Autodesk Inventor part; units mm, degrees
(part 2 of 2)
sketch "Sketch22" plane through (0, 5, 0) normal (0, 1, 0) x (1, 0, 0)
  circle A0 centre (-16, 40) radius 1.75 projected
  circle A1 centre (-21.2113, 35) radius 1.25 projected
  circle A2 centre (-21.2113, 15) radius 1.25 projected
  circle A3 centre (-16, 10) radius 1.75 projected
  circle A4 centre (-41.2113, 15) radius 1.25 projected
  circle A5 centre (-41.2113, 35) radius 1.25 projected
  circle A6 centre (-46.8088, 40.126) radius 1.75 projected
  circle A7 centre (-46.8088, 9.874) radius 1.75 projected
  circle A8 centre (-67.6238, 7.0035) radius 1.75 projected
  circle A9 centre (-78.624, 10.0035) radius 2.25 projected
  circle A10 centre (-78.624, 39.9965) radius 2.25 projected
  circle A11 centre (-67.6238, 42.9965) radius 1.75 projected
  circle A12 centre (-83.6239, 34.9965) radius 1.75 projected
  circle A13 centre (-83.6239, 15.0035) radius 1.75 projected
  circle A14 centre (-103.6239, 15.0035) radius 1.75 projected
  circle A15 centre (-108.6238, 10.0035) radius 2.25 projected
  circle A16 centre (-103.6239, 34.9965) radius 1.75 projected
  circle A17 centre (-108.6238, 39.9965) radius 2.25 projected
  circle A18 centre (-119.6241, 42.9965) radius 1.75 projected
  circle A19 centre (-119.6241, 7.0035) radius 1.75 projected
  circle A20 centre (-190.57, 135.7115) radius 3.625 projected
  arc A21 (-199.1108, 135.8702) -> (-198.6468, 138.4891) centre (-198.448, 137.1033) ccw projected
  arc A22 (-199.1108, 135.8702) -> (-199.7262, 135.9792) centre (-199.5842, 134.9893) ccw projected
  arc A23 (-199.2622, 138.5982) -> (-198.6468, 138.4891) centre (-198.7888, 139.479) ccw projected
  arc A24 (-199.2622, 138.5982) -> (-199.7262, 135.9792) centre (-199.925, 137.365) ccw projected
  arc A25 (-190.7287, 127.1707) -> (-193.3476, 127.6347) centre (-191.9618, 127.8335) ccw projected
  arc A26 (-190.7287, 127.1707) -> (-190.8377, 126.5553) centre (-189.8478, 126.6973) ccw projected
  arc A27 (-193.4567, 127.0193) -> (-190.8377, 126.5553) centre (-192.2235, 126.3565) ccw projected
  arc A28 (-193.4567, 127.0193) -> (-193.3476, 127.6347) centre (-194.3375, 127.4927) ccw projected
  arc A29 (-182.0292, 135.5529) -> (-182.4932, 132.9339) centre (-182.692, 134.3197) ccw projected
  arc A30 (-181.8778, 132.8249) -> (-182.4932, 132.9339) centre (-182.3512, 131.944) ccw projected
  arc A31 (-181.8778, 132.8249) -> (-181.4138, 135.4439) centre (-181.215, 134.0581) ccw projected
  arc A32 (-182.0292, 135.5529) -> (-181.4138, 135.4439) centre (-181.5558, 136.4337) ccw projected
  arc A33 (-187.6834, 144.4037) -> (-187.7924, 143.7883) centre (-186.8025, 143.9303) ccw projected
  arc A34 (-187.6834, 144.4037) -> (-190.3024, 144.8677) centre (-188.9166, 145.0665) ccw projected
  arc A35 (-190.4114, 144.2523) -> (-187.7924, 143.7883) centre (-189.1782, 143.5895) ccw projected
  arc A36 (-190.4114, 144.2523) -> (-190.3024, 144.8677) centre (-191.2922, 144.7257) ccw projected
  circle A37 centre (30.57, 135.7115) radius 3.625 projected
  arc A38 (38.6468, 138.4891) -> (39.1108, 135.8702) centre (38.448, 137.1033) ccw projected
  arc A39 (39.7262, 135.9792) -> (39.1108, 135.8702) centre (39.5842, 134.9893) ccw projected
  arc A40 (38.6468, 138.4891) -> (39.2622, 138.5982) centre (38.7888, 139.479) ccw projected
  arc A41 (39.7262, 135.9792) -> (39.2622, 138.5982) centre (39.925, 137.365) ccw projected
  arc A42 (33.3476, 127.6347) -> (30.7287, 127.1707) centre (31.9618, 127.8335) ccw projected
  arc A43 (33.3476, 127.6347) -> (33.4567, 127.0193) centre (34.3375, 127.4927) ccw projected
  arc A44 (30.8377, 126.5553) -> (30.7287, 127.1707) centre (29.8478, 126.6973) ccw projected
  arc A45 (30.8377, 126.5553) -> (33.4567, 127.0193) centre (32.2235, 126.3565) ccw projected
  arc A46 (27.7924, 143.7883) -> (30.4114, 144.2523) centre (29.1782, 143.5895) ccw projected
  arc A47 (30.3024, 144.8677) -> (30.4114, 144.2523) centre (31.2922, 144.7257) ccw projected
  arc A48 (27.7924, 143.7883) -> (27.6834, 144.4037) centre (26.8025, 143.9303) ccw projected
  arc A49 (30.3024, 144.8677) -> (27.6834, 144.4037) centre (28.9166, 145.0665) ccw projected
  arc A50 (22.4932, 132.9339) -> (22.0292, 135.5529) centre (22.692, 134.3197) ccw projected
  arc A51 (21.4138, 135.4439) -> (22.0292, 135.5529) centre (21.5558, 136.4337) ccw projected
  arc A52 (22.4932, 132.9339) -> (21.8778, 132.8249) centre (22.3512, 131.944) ccw projected
  arc A53 (21.4138, 135.4439) -> (21.8778, 132.8249) centre (21.215, 134.0581) ccw projected
  circle A54 centre (30.57, -85.7115) radius 3.625 projected
  arc A55 (39.1108, -85.8702) -> (38.6468, -88.4891) centre (38.448, -87.1033) ccw projected
  arc A56 (39.2622, -88.5982) -> (39.7262, -85.9792) centre (39.925, -87.365) ccw projected
  arc A57 (39.1108, -85.8702) -> (39.7262, -85.9792) centre (39.5842, -84.9893) ccw projected
  arc A58 (39.2622, -88.5982) -> (38.6468, -88.4891) centre (38.7888, -89.479) ccw projected
  arc A59 (30.4114, -94.2523) -> (27.7924, -93.7883) centre (29.1782, -93.5895) ccw projected
  arc A60 (30.4114, -94.2523) -> (30.3024, -94.8677) centre (31.2922, -94.7257) ccw projected
  arc A61 (27.6834, -94.4037) -> (30.3024, -94.8677) centre (28.9166, -95.0665) ccw projected
  arc A62 (27.6834, -94.4037) -> (27.7924, -93.7883) centre (26.8025, -93.9303) ccw projected
  arc A63 (30.7287, -77.1707) -> (33.3476, -77.6347) centre (31.9618, -77.8335) ccw projected
  arc A64 (33.4567, -77.0193) -> (33.3476, -77.6347) centre (34.3375, -77.4927) ccw projected
  arc A65 (33.4567, -77.0193) -> (30.8377, -76.5553) centre (32.2235, -76.3565) ccw projected
  arc A66 (30.7287, -77.1707) -> (30.8377, -76.5553) centre (29.8478, -76.6973) ccw projected
  arc A67 (22.0292, -85.5529) -> (22.4932, -82.9339) centre (22.692, -84.3197) ccw projected
  arc A68 (21.8778, -82.8249) -> (22.4932, -82.9339) centre (22.3512, -81.944) ccw projected
  arc A69 (22.0292, -85.5529) -> (21.4138, -85.4439) centre (21.5558, -86.4337) ccw projected
  arc A70 (21.8778, -82.8249) -> (21.4138, -85.4439) centre (21.215, -84.0581) ccw projected
  circle A71 centre (-190.57, -85.7115) radius 3.625 projected
  arc A72 (-187.7924, -93.7883) -> (-190.4114, -94.2523) centre (-189.1782, -93.5895) ccw projected
  arc A73 (-187.7924, -93.7883) -> (-187.6834, -94.4037) centre (-186.8025, -93.9303) ccw projected
  arc A74 (-190.3024, -94.8677) -> (-187.6834, -94.4037) centre (-188.9166, -95.0665) ccw projected
  arc A75 (-190.3024, -94.8677) -> (-190.4114, -94.2523) centre (-191.2922, -94.7257) ccw projected
  arc A76 (-198.6468, -88.4891) -> (-199.1108, -85.8702) centre (-198.448, -87.1033) ccw projected
  arc A77 (-198.6468, -88.4891) -> (-199.2622, -88.5982) centre (-198.7888, -89.479) ccw projected
  arc A78 (-199.7262, -85.9792) -> (-199.1108, -85.8702) centre (-199.5842, -84.9893) ccw projected
  arc A79 (-199.7262, -85.9792) -> (-199.2622, -88.5982) centre (-199.925, -87.365) ccw projected
  arc A80 (-190.8377, -76.5553) -> (-190.7287, -77.1707) centre (-189.8478, -76.6973) ccw projected
  arc A81 (-193.3476, -77.6347) -> (-190.7287, -77.1707) centre (-191.9618, -77.8335) ccw projected
  arc A82 (-190.8377, -76.5553) -> (-193.4567, -77.0193) centre (-192.2235, -76.3565) ccw projected
  arc A83 (-193.3476, -77.6347) -> (-193.4567, -77.0193) centre (-194.3375, -77.4927) ccw projected
  arc A84 (-181.4138, -85.4439) -> (-181.8778, -82.8249) centre (-181.215, -84.0581) ccw projected
  arc A85 (-181.4138, -85.4439) -> (-182.0292, -85.5529) centre (-181.5558, -86.4337) ccw projected
  arc A86 (-182.4932, -82.9339) -> (-181.8778, -82.8249) centre (-182.3512, -81.944) ccw projected
  arc A87 (-182.4932, -82.9339) -> (-182.0292, -85.5529) centre (-182.692, -84.3197) ccw projected
  point P0 (0, 0)
extrude "Extrusion24" add sketch "Sketch22" against normal blind 5 separate body
sketch "Sketch23" plane through (0, -30, 0) normal (0, -1, 0) x (1, 0, 0)
  circle A0 centre (-68.684, -20) radius 1.75 projected
  circle A1 centre (-68.684, -30) radius 1.75 projected
  circle A2 centre (-118.0644, -20.0035) radius 1.75 projected
  circle A3 centre (-118.0644, -29.9965) radius 1.75 projected
  point P0 (0, 0)
extrude "Extrusion25" add sketch "Sketch23" against normal blind 5 separate body
ref_plane "Work Plane4" through (-160, 0, 0) normal (1, 0, 0) x (0, 1, 0)
ref_plane "Work Plane5" through (-160, 0, -50) normal (-1, 0, 0) x (0, 1, 0)
equation "\"d21\" = d19"
equation "\"d24\" = d16"
equation "\"d27\" = d16"
equation "\"d33\" = d16"
equation "\"d35\" = d16"
equation "\"d37\" = d30"
equation "\"d40\" = d16"
equation "\"d52\" = d49"
equation "\"d87\" = d30"
equation "\"d89\" = d30"
equation "\"d92\" = d30"
equation "\"d95\" = d30"
equation "\"d109\" = d16"
equation "\"d114\" = d16"
equation "\"d117\" = d16"
equation "\"d120\" = d16"
body "Solid1"
